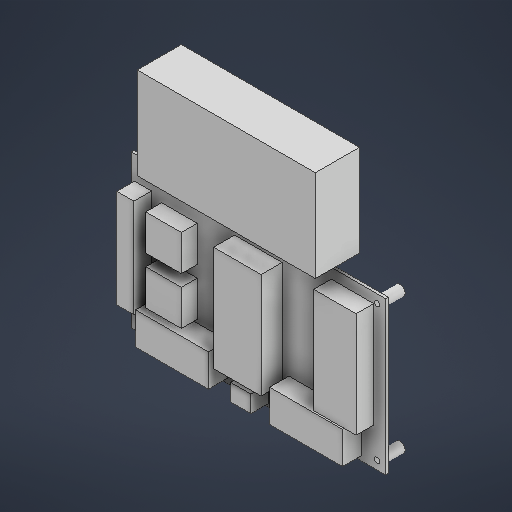
# Autodesk Inventor part: 03_Bo_Mach_PCB_150x90_Altium
Saved by Autodesk Inventor 2027.1 (Build 311270010, 270A)
## iProperties
Created: 2026-11-18
Part Number: 03_Bo_Mach_PCB_150x90_Altium
Material: Generic
Document SubType Name: Modeling
Designer: cuong
Density: 1 g/cm^3
Appearance: Default
Author: cuong
Autodesk Inventor part; units mm, degrees
ref_plane "Work Plane1" through (0, 0, 44) normal (0, 0, 1) x (1, 0, 0)
sketch "Sketch1" plane through (0, 0, 44) normal (0, 0, 1) x (1, 0, 0)
  line L0 (125, 55) -> (275, 55)
  line L1 (275, 55) -> (275, 145)
  line L2 (275, 145) -> (125, 145)
  line L3 (125, 145) -> (125, 55)
  constraints: 8 end point, 2 parallel, 1 horizontal, 1 perpendicular
extrude "Extrusion1" add sketch "Sketch1" along normal blind 1.6
ref_plane "Work Plane2" through (0, 0, 32) normal (0, 0, 1) x (1, 0, 0)
sketch "Sketch2" plane through (0, 0, 32) normal (0, 0, 1) x (1, 0, 0)
  circle A0 centre (130, 60) radius 3
  constraints: 1 centre point
extrude "Extrusion2" add sketch "Sketch2" along normal blind 12
ref_plane "Work Plane3" through (0, 0, 43) normal (0, 0, 1) x (1, 0, 0)
sketch "Sketch3" plane through (0, 0, 43) normal (0, 0, 1) x (1, 0, 0)
  circle A0 centre (130, 60) radius 1.6
  constraints: 1 centre point
extrude "Extrusion3" cut sketch "Sketch3" along normal blind 4
ref_plane "Work Plane4" through (0, 0, 32) normal (0, 0, 1) x (1, 0, 0)
sketch "Sketch4" plane through (0, 0, 32) normal (0, 0, 1) x (1, 0, 0)
  circle A0 centre (130, 140) radius 3
  constraints: 1 centre point
extrude "Extrusion4" add sketch "Sketch4" along normal blind 12
ref_plane "Work Plane5" through (0, 0, 43) normal (0, 0, 1) x (1, 0, 0)
sketch "Sketch5" plane through (0, 0, 43) normal (0, 0, 1) x (1, 0, 0)
  circle A0 centre (130, 140) radius 1.6
  constraints: 1 centre point
extrude "Extrusion5" cut sketch "Sketch5" along normal blind 4
ref_plane "Work Plane6" through (0, 0, 32) normal (0, 0, 1) x (1, 0, 0)
sketch "Sketch6" plane through (0, 0, 32) normal (0, 0, 1) x (1, 0, 0)
  circle A0 centre (270, 60) radius 3
  constraints: 1 centre point
extrude "Extrusion6" add sketch "Sketch6" along normal blind 12
ref_plane "Work Plane7" through (0, 0, 43) normal (0, 0, 1) x (1, 0, 0)
sketch "Sketch7" plane through (0, 0, 43) normal (0, 0, 1) x (1, 0, 0)
  circle A0 centre (270, 60) radius 1.6
  constraints: 1 centre point
extrude "Extrusion7" cut sketch "Sketch7" along normal blind 4
ref_plane "Work Plane8" through (0, 0, 32) normal (0, 0, 1) x (1, 0, 0)
sketch "Sketch8" plane through (0, 0, 32) normal (0, 0, 1) x (1, 0, 0)
  circle A0 centre (270, 140) radius 3
  constraints: 1 centre point
extrude "Extrusion8" add sketch "Sketch8" along normal blind 12
ref_plane "Work Plane9" through (0, 0, 43) normal (0, 0, 1) x (1, 0, 0)
sketch "Sketch9" plane through (0, 0, 43) normal (0, 0, 1) x (1, 0, 0)
  circle A0 centre (270, 140) radius 1.6
  constraints: 1 centre point
extrude "Extrusion9" cut sketch "Sketch9" along normal blind 4
ref_plane "Work Plane10" through (0, 0, 45.6) normal (0, 0, 1) x (1, 0, 0)
sketch "Sketch10" plane through (0, 0, 45.6) normal (0, 0, 1) x (1, 0, 0)
  line L0 (186, 71) -> (214, 71)
  line L1 (214, 71) -> (214, 133)
  line L2 (214, 133) -> (186, 133)
  line L3 (186, 133) -> (186, 71)
  constraints: 8 end point, 2 parallel, 1 horizontal, 1 perpendicular
extrude "Extrusion10" add sketch "Sketch10" along normal blind 12.4
ref_plane "Work Plane11" through (0, 0, 45.6) normal (0, 0, 1) x (1, 0, 0)
sketch "Sketch11" plane through (0, 0, 45.6) normal (0, 0, 1) x (1, 0, 0)
  line L0 (143, 79) -> (164, 79)
  line L1 (164, 79) -> (164, 100)
  line L2 (164, 100) -> (143, 100)
  line L3 (143, 100) -> (143, 79)
  constraints: 8 end point, 2 parallel, 1 horizontal, 1 perpendicular
extrude "Extrusion11" add sketch "Sketch11" along normal blind 9.4
ref_plane "Work Plane12" through (0, 0, 45.6) normal (0, 0, 1) x (1, 0, 0)
sketch "Sketch12" plane through (0, 0, 45.6) normal (0, 0, 1) x (1, 0, 0)
  line L0 (143, 107) -> (164, 107)
  line L1 (164, 107) -> (164, 128)
  line L2 (164, 128) -> (143, 128)
  line L3 (143, 128) -> (143, 107)
  constraints: 8 end point, 2 parallel, 1 horizontal, 1 perpendicular
extrude "Extrusion12" add sketch "Sketch12" along normal blind 9.4
ref_plane "Work Plane13" through (0, 0, 45.6) normal (0, 0, 1) x (1, 0, 0)
sketch "Sketch13" plane through (0, 0, 45.6) normal (0, 0, 1) x (1, 0, 0)
  line L0 (127, 73) -> (137, 73)
  line L1 (137, 73) -> (137, 131)
  line L2 (137, 131) -> (127, 131)
  line L3 (127, 131) -> (127, 73)
  constraints: 8 end point, 2 parallel, 1 horizontal, 1 perpendicular
extrude "Extrusion13" add sketch "Sketch13" along normal blind 10.4
ref_plane "Work Plane14" through (0, 0, 45.6) normal (0, 0, 1) x (1, 0, 0)
sketch "Sketch14" plane through (0, 0, 45.6) normal (0, 0, 1) x (1, 0, 0)
  line L0 (139, 58) -> (182, 58)
  line L1 (182, 58) -> (182, 77)
  line L2 (182, 77) -> (139, 77)
  line L3 (139, 77) -> (139, 58)
  constraints: 8 end point, 2 parallel, 1 horizontal, 1 perpendicular
extrude "Extrusion14" add sketch "Sketch14" along normal blind 11.4
ref_plane "Work Plane15" through (0, 0, 45.6) normal (0, 0, 1) x (1, 0, 0)
sketch "Sketch15" plane through (0, 0, 45.6) normal (0, 0, 1) x (1, 0, 0)
  line L0 (218, 58) -> (261, 58)
  line L1 (261, 58) -> (261, 77)
  line L2 (261, 77) -> (218, 77)
  line L3 (218, 77) -> (218, 58)
  constraints: 8 end point, 2 parallel, 1 horizontal, 1 perpendicular
extrude "Extrusion15" add sketch "Sketch15" along normal blind 11.4
ref_plane "Work Plane16" through (0, 0, 45.6) normal (0, 0, 1) x (1, 0, 0)
sketch "Sketch16" plane through (0, 0, 45.6) normal (0, 0, 1) x (1, 0, 0)
  line L0 (194, 57) -> (206, 57)
  line L1 (206, 57) -> (206, 67)
  line L2 (206, 67) -> (194, 67)
  line L3 (194, 67) -> (194, 57)
  constraints: 8 end point, 2 parallel, 1 horizontal, 1 perpendicular
extrude "Extrusion16" add sketch "Sketch16" along normal blind 10.4
ref_plane "Work Plane17" through (0, 0, 45.6) normal (0, 0, 1) x (1, 0, 0)
sketch "Sketch17" plane through (0, 0, 45.6) normal (0, 0, 1) x (1, 0, 0)
  line L0 (243, 77) -> (268, 77)
  line L1 (268, 77) -> (268, 139)
  line L2 (268, 139) -> (243, 139)
  line L3 (243, 139) -> (243, 77)
  constraints: 8 end point, 2 parallel, 1 horizontal, 1 perpendicular
extrude "Extrusion17" add sketch "Sketch17" along normal blind 10.4
ref_plane "Work Plane18" through (0, 0, 36) normal (0, 0, 1) x (1, 0, 0)
sketch "Sketch18" plane through (0, 0, 36) normal (0, 0, 1) x (1, 0, 0)
  line L0 (145, 151) -> (250, 151)
  line L1 (250, 151) -> (250, 205)
  line L2 (250, 205) -> (145, 205)
  line L3 (145, 205) -> (145, 151)
  constraints: 8 end point, 2 parallel, 1 horizontal, 1 perpendicular
extrude "Extrusion18" add sketch "Sketch18" along normal blind 26
body "Solid1"
